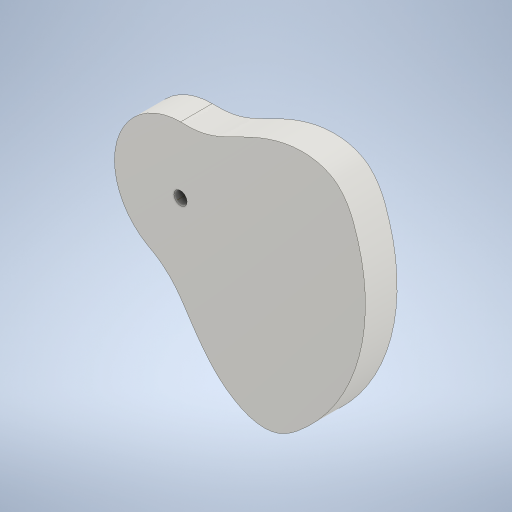
# Autodesk Inventor part: Leva de disco
Saved by Autodesk Inventor 2024 (Build 280153000, 153)
## iProperties
CustomPartVersion: 1
Created: 2024-05-21
Part Number: Leva de disco
Material: Stainless Steel, Austenitic
Document SubType Name: Modeling
Designer: PC
Manufacturer: Standard
Standards Organization: Custom
Density: 1 g/cm^3
Appearance: Steel
Author: PC
Autodesk Inventor part; units mm, degrees
ref_plane "YZ Plane" through (0, 0, 0) normal (1, 0, 0) x (0, 1, 0)
ref_plane "XZ Plane" through (0, 0, 0) normal (0, 1, 0) x (-1, 0, 0)
ref_plane "XY Plane" through (0, 0, 0) normal (0, 0, 1) x (1, 0, 0)
sketch "Boceto principal" plane through (0, 0, 0) normal (0, 0, 1) x (1, 0, 0)
  spline S0 degree 5 poles (0.0239, 25) (0.669, 25.0025) (1.7617, 24.9829) (3.5239, 24.9353) (6.5872, 25.202) (8.5802, 25.5684) (13.2439, 26.677) (18.6621, 29.334) (24.3951, 32.2812) (32.7136, 36.3311) (43.0721, 38.8687) (51.4251, 38.4346) (59.6872, 35.8117) (64.5694, 28.0878) (66.4828, 22.128) (68.7702, 14.4625) (69.7616, 7.3138) (70.2298, -0.0182) (69.7518, -7.6559) (68.7059, -14.3131) (66.7636, -21.7393) (64.1125, -28.5329) (60.8088, -35.1037) (56.6318, -41.4478) (52.2619, -46.8539) (47.0838, -52.0142) (40.5817, -57.5764) (34.1369, -60.2814) (25.2921, -59.5895) (16.4035, -53.8234) (10.683, -48.337) (4.3393, -39.3266) (0.8979, -33.663) (-2.3429, -29.3715) (-5.1238, -26.5682) (-7.7814, -24.404) (-10.8519, -22.5186) (-12.261, -21.8574) (-14.9168, -20.1797) (-16.8136, -18.563) (-18.5834, -16.8334) (-20.2801, -14.7358) (-21.7003, -12.5558) (-22.9101, -10.1713) (-23.8444, -7.7582) (-24.5417, -5.0943) (-24.9142, -2.7218) (-25.0779, 0.0148) (-24.9237, 2.6196) (-24.533, 5.1995) (-23.8037, 7.8424) (-22.9467, 10.0853) (-21.7092, 12.5465) (-20.2972, 14.7116) (-18.6099, 16.7949) (-16.7864, 18.6263) (-14.6348, 20.3484) (-12.6225, 21.6528) (-10.179, 22.9172) (-7.8496, 23.7987) (-5.2925, 24.5053) (-3.2029, 24.8394) (-1.6285, 24.9717) (-0.5978, 24.9976) (0.0239, 25) knots 0 0 0 0 0 0 0.015562 0.026183 0.040544 0.056388 0.074321 0.095064 0.117481 0.140541 0.163864 0.186373 0.207912 0.229041 0.249994 0.270836 0.291744 0.312653 0.333561 0.35447 0.375379 0.396287 0.417196 0.438254 0.45915 0.480221 0.502136 0.524736 0.548078 0.571429 0.59375 0.614094 0.632422 0.648273 0.662218 0.675325 0.688003 0.70024 0.712368 0.724863 0.737359 0.749854 0.762429 0.774924 0.78742 0.799915 0.81241 0.824906 0.837401 0.849896 0.862391 0.874887 0.887382 0.899957 0.912452 0.924948 0.937443 0.949938 0.962433 0.974977 0.985005 1 1 1 1 1 1
  point P0 (5.9174, 25.184)
  point P1 (8.2397, 25.5446)
  point P2 (11.7478, 26.4614)
  point P3 (17.1746, 28.654)
  point P4 (23.3534, 31.7105)
  point P5 (32.2594, 35.6181)
  point P6 (43.1851, 38.1862)
  point P7 (52.0966, 37.6906)
  point P8 (59.3543, 34.2275)
  point P9 (64.0805, 28.0084)
  point P10 (66.5348, 21.7514)
  point P11 (68.4616, 14.595)
  point P12 (69.6209, 7.2751)
  point P13 (69.9999, -0.1264)
  point P14 (69.5942, -7.5264)
  point P15 (68.5052, -14.3889)
  point P16 (66.5999, -21.551)
  point P17 (63.9482, -28.4716)
  point P18 (60.5796, -35.0729)
  point P19 (56.532, -41.2812)
  point P20 (52.1608, -46.6824)
  point P21 (46.933, -51.9355)
  point P22 (40.6666, -56.8261)
  point P23 (34.2886, -59.319)
  point P24 (26.2717, -58.6893)
  point P25 (17.3252, -53.9409)
  point P26 (10.1284, -46.9759)
  point P27 (3.7269, -38.1677)
  point P28 (-0.1177, -32.4653)
  point P29 (-3.0568, -28.7902)
  point P30 (-5.6365, -26.2421)
  point P31 (-8.3732, -24.1248)
  point P32 (-10.8197, -22.6005)
  point P33 (-12.4997, -21.6508)
  point P34 (-14.719, -20.2077)
  point P35 (-16.7729, -18.5383)
  point P36 (-18.5282, -16.7841)
  point P37 (-20.1989, -14.7311)
  point P38 (-21.6431, -12.513)
  point P39 (-22.8448, -10.1547)
  point P40 (-23.7903, -7.6825)
  point P41 (-24.4692, -5.1242)
  point P42 (-24.8567, -2.6731)
  point P43 (-25, -0.0301)
  point P44 (-24.863, 2.6132)
  point P45 (-24.4474, 5.2272)
  point P46 (-23.7577, 7.7826)
  point P47 (-22.8691, 10.0996)
  point P48 (-21.6732, 12.4609)
  point P49 (-20.2343, 14.6825)
  point P50 (-18.5685, 16.7394)
  point P51 (-16.6947, 18.6088)
  point P52 (-14.6337, 20.2696)
  point P53 (-12.5521, 21.6205)
  point P54 (-10.1959, 22.8264)
  point P55 (-7.7254, 23.7764)
  point P56 (-5.1684, 24.4599)
  point P57 (-2.5533, 24.8693)
  constraints: 60 other
extrude "Leva" add sketch "Boceto principal" along normal blind 12
sketch "Boceto2" plane through (0, 0, 12) normal (0, 0, 1) x (1, 0, 0)
  circle A0 centre (0, 0) radius 2.5
  dimension "d4" = 5
  constraints: 1 centre point, 1 coincident
  measures "d4" diameter of A0
extrude "Extrusión2" cut sketch "Boceto2" against normal through all
body "Solid1"
